Nut (Autodesk Fusion 360 design; units mm, degrees)
Autodesk Fusion 360 part; units mm, degrees
sketch "Sketch3" plane through (0, 0, 40) normal (0, 0, 1) x (1, 0, 0)
  circle A0 centre (0, 0) radius 5
  line L0 (0, 0) -> (0, -8)
  line L1 (0, 0) -> (0, 8)
  line L2 (0, 0) -> (6.9282, 4)
  line L3 (0, 0) -> (6.9282, -4)
  line L4 (0, 0) -> (-6.9282, -4)
  line L5 (0, 0) -> (-6.9282, 4)
  line L6 (-9.2376, 0) -> (-4.6188, -8)
  line L7 (-4.6188, -8) -> (4.6188, -8)
  line L8 (4.6188, -8) -> (9.2319, -0.0099)
  line L9 (9.2319, -0.0099) -> (4.6188, 8)
  line L10 (4.6188, 8) -> (-4.6188, 8)
  line L11 (-4.6188, 8) -> (-9.2376, 0)
  constraint coincident A0.centre L0.start
  constraint parallel L3 L5
extrude "Extrude3" add sketch "Sketch3" along normal blind 8
sketch "Sketch4" plane through (0, 0, 48) normal (0, 0, 1) x (1, 0, 0)
  line L0 (-4.6188, 8) -> (-9.2376, 0)
  line L1 (-9.2376, 0) -> (-4.6188, -8)
  line L2 (-4.6188, -8) -> (4.6188, -8)
  line L3 (4.6188, -8) -> (9.2319, -0.0099)
  line L4 (9.2319, -0.0099) -> (4.6188, 8)
  line L5 (4.6188, 8) -> (-4.6188, 8)
  circle A0 centre (0, 0) radius 5
  dimension "d27" = 10
  constraint coincident A0.centre origin
  measures "d27" diameter of A0
extrude "Extrude4" cut sketch "Sketch4" against normal up to surface (8 mm away) contours A0
thread "Thread2" "ISO Metric profile 10.0 M10x1.5 6H" major diameter 10.198 minor diameter 8.526 pitch 1.5 angle 60 modelled right hand crest width 0.1875 on face at (4.9752, -0.4978, 45.3333) crest through (4.263, 0, 48.8438)
